Autodesk Fusion 360 part; units mm, degrees
(part 16 of 18)
extrude "Extrude1" add sketch "8x8-Edge_Cuts" along normal blind 2 contours L11 L12 L13 L14